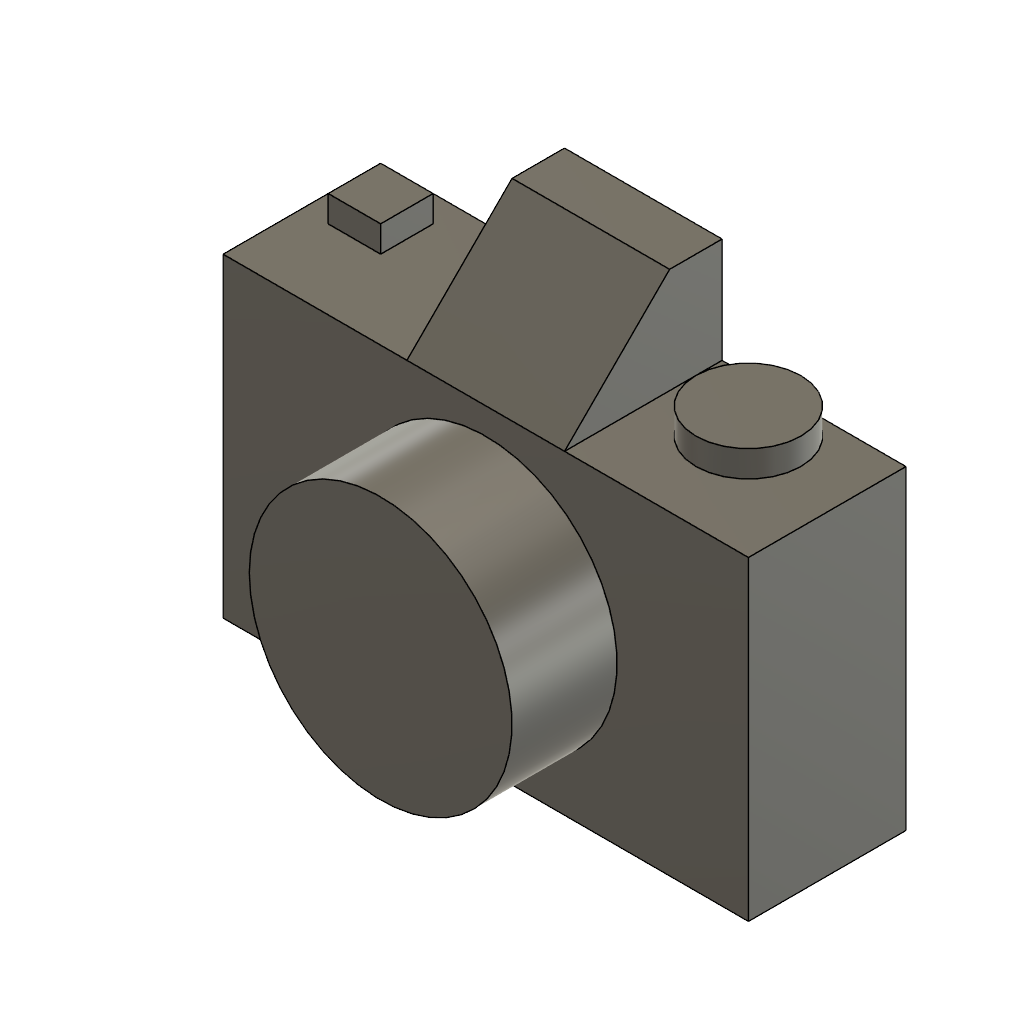
26015028 exercise 2.1(nithish R) (Autodesk Fusion 360 design; units mm, degrees)
part number: 2026-10-06-15-01-25-773
Autodesk Fusion 360 part; units mm, degrees
sketch "Sketch1" plane through (0, 0, 0) normal (0, 0, 1) x (1, 0, 0)
  line L0 (50, -30) -> (-50, -30)
  line L1 (-50, -30) -> (-50, 30)
  line L2 (-50, 30) -> (50, 30)
  line L3 (50, 30) -> (50, -30)
  line L4 (50, -30) -> (-50, 30) construction
  line L5 (-50, -30) -> (50, 30) construction
  dimension "d1" = 100
  dimension "d2" = 60
  constraint horizontal L0
  constraint perpendicular L0 L1
  constraint parallel L0 L2
  constraint parallel L1 L3
  constraint coincident L4 origin
  constraint coincident L5 origin
  measures "d1" distance of L1.end L2.end
  measures "d2" distance of L0.end L1.end
extrude "Extrude1" add sketch "Sketch1" along normal blind 30
sketch "Sketch2" plane through (0, 0, 30) normal (0, 0, 1) x (1, 0, 0)
  line L0 (50, 30) -> (-50, 30)
  line L1 (-50, 30) -> (-50, -30)
  line L2 (-50, -30) -> (50, -30)
  line L3 (50, -30) -> (50, 30)
  circle A0 centre (0, 0) radius 25
  dimension "d5" = 50
  constraint coincident A0.centre origin
  measures "d5" diameter of A0
extrude "Extrude2" add sketch "Sketch2" along normal blind 20 contours A0
sketch "Sketch3" plane through (0, 30, 0) normal (0, 1, 0) x (-1, 0, 0)
  line L0 (-50, 0) -> (50, 0)
  line L1 (50, 0) -> (50, 30)
  line L2 (50, 30) -> (-50, 30)
  line L3 (-50, 30) -> (-50, 0)
  line L4 (35, 15) -> (45, 15)
  line L5 (45, 15) -> (45, 5)
  line L6 (45, 5) -> (35, 5)
  line L7 (35, 5) -> (35, 15)
  line L8 (35, 15) -> (45, 5) construction
  line L9 (45, 15) -> (35, 5) construction
  circle A0 centre (-30, 10) radius 10
  point P0 (40, 10)
  dimension "d8" = 10
  dimension "d9" = 10
  dimension "d10" = 20
  constraint horizontal L4
  constraint perpendicular L4 L5
  constraint parallel L4 L6
  constraint parallel L5 L7
  constraint coincident L8 P0
  constraint coincident L9 P0
  measures "d8" distance of L5.end L6.end
  measures "d9" distance of L4.end L5.end
  measures "d10" diameter of A0
extrude "Extrude3" add sketch "Sketch3" along normal blind 5 contours L4 L5 L6 L7
sketch "Sketch4" plane through (0, 30, 0) normal (0, 1, 0) x (-1, 0, 0)
  line L0 (35, 5) -> (35, 15)
  line L1 (35, 15) -> (45, 15)
  line L2 (45, 15) -> (45, 5)
  line L3 (45, 5) -> (35, 5)
  line L4 (-50, 0) -> (50, 0)
  line L5 (50, 0) -> (50, 30)
  line L6 (50, 30) -> (-50, 30)
  line L7 (-50, 30) -> (-50, 0)
  circle A0 centre (-30, 10) radius 10
  dimension "d13" = 20
  measures "d13" diameter of A0
extrude "Extrude4" add sketch "Sketch4" along normal blind 5 contours A0
sketch "Sketch5" plane through (0, 30, 0) normal (0, 1, 0) x (-1, 0, 0)
  line L0 (-30, 0) -> (50, 0)
  line L1 (50, 0) -> (50, 30)
  line L2 (50, 30) -> (-50, 30)
  line L3 (-50, 30) -> (-50, 0)
  line L4 (-50, 0) -> (-30, 0)
  circle A0 centre (-30, 10) radius 10
  line L5 (35, 5) -> (35, 15)
  line L6 (35, 15) -> (45, 15)
  line L7 (45, 15) -> (45, 5)
  line L8 (45, 5) -> (35, 5)
  line L9 (-15, 0) -> (15, 0)
  line L10 (15, 0) -> (15, 10)
  line L11 (15, 10) -> (-15, 10)
  line L12 (-15, 10) -> (-15, 0)
  dimension "d16" = 30
  constraint horizontal L9
  constraint vertical L10
  constraint horizontal L11
  constraint vertical L12
  constraint coincident L0 L9.start
  measures "d16" distance of L9.start L9.end
sketch "Sketch6" plane through (0, 30, 0) normal (0, 1, 0) x (-1, 0, 0)
extrude "Extrude5" add sketch "Sketch5" along normal blind 20 contours L0 L9 L10 L11 L12
sketch "Sketch7" plane through (15, 0, 0) normal (1, 0, 0) x (0, 0, -1)
  line L0 (-10, 30) -> (0, 30)
  line L1 (0, 30) -> (0, 50)
  line L2 (0, 50) -> (-10, 50)
  line L3 (-10, 50) -> (-10, 30)
  line L4 (-10, 50) -> (-30, 30)
  line L5 (-30, 30) -> (-10, 30)
  constraint coincident L2.end L3.start
  constraint coincident L0.start L3.end
  constraint perpendicular L3 L5
extrude "Extrude6" add sketch "Sketch7" against normal blind 30 contours L3 L4 L5
